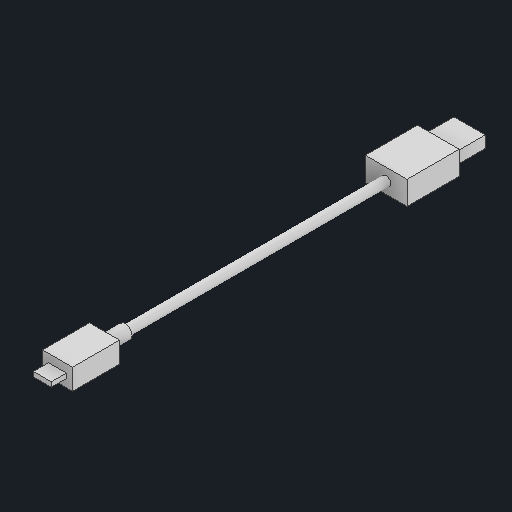
# Autodesk Inventor part: test_cable_microUSB_to_USBA
Saved by Autodesk Inventor 2027.1 (Build 311270010, 270A)
## iProperties
Created: 2026-10-29
Part Number: test_cable_microUSB_to_USBA
Material: Generic
Document SubType Name: Modeling
Designer: alexg
Density: 1 g/cm^3
Appearance: Default
Author: alexg
Autodesk Inventor part; units mm, degrees
ref_plane "Work Plane1" through (0, 0, -25.5) normal (0, 0, 1) x (1, 0, 0)
sketch "Micro-B shell sketch" plane through (0, 0, -25.5) normal (0, 0, 1) x (1, 0, 0)
  line L0 (-27.425, -26.74) -> (-20.575, -26.74)
  line L1 (-20.575, -26.74) -> (-20.575, -24.94)
  line L2 (-20.575, -24.94) -> (-27.425, -24.94)
  line L3 (-27.425, -24.94) -> (-27.425, -26.74)
  constraints: 8 end point, 2 parallel, 1 horizontal, 1 perpendicular
extrude "Micro-B shell" add sketch "Micro-B shell sketch" along normal blind 5.8
ref_plane "Work Plane2" through (0, 0, -25.5) normal (0, 0, 1) x (1, 0, 0)
sketch "Overmould 11.5x8x18 sketch" plane through (0, 0, -25.5) normal (0, 0, 1) x (1, 0, 0)
  line L0 (-29.75, -29.84) -> (-18.25, -29.84)
  line L1 (-18.25, -29.84) -> (-18.25, -21.84)
  line L2 (-18.25, -21.84) -> (-29.75, -21.84)
  line L3 (-29.75, -21.84) -> (-29.75, -29.84)
  constraints: 8 end point, 2 parallel, 1 horizontal, 1 perpendicular
extrude "Overmould 11.5x8x18" add sketch "Overmould 11.5x8x18 sketch" against normal blind 18
ref_plane "Work Plane3" through (0, 0, -43.5) normal (0, 0, 1) x (1, 0, 0)
sketch "Strain relief sketch" plane through (0, 0, -43.5) normal (0, 0, 1) x (1, 0, 0)
  circle A0 centre (-24, -25.84) radius 2.6
  constraints: 1 centre point
extrude "Strain relief" add sketch "Strain relief sketch" against normal blind 8
ref_plane "Work Plane4" through (0, 0, -51.5) normal (0, 0, 1) x (1, 0, 0)
sketch "Cable sketch" plane through (0, 0, -51.5) normal (0, 0, 1) x (1, 0, 0)
  circle A0 centre (-24, -25.84) radius 1.75
  constraints: 1 centre point
extrude "Cable" add sketch "Cable sketch" against normal blind 100
ref_plane "Work Plane5" through (0, 0, -151.5) normal (0, 0, 1) x (1, 0, 0)
sketch "USB-A overmould sketch" plane through (0, 0, -151.5) normal (0, 0, 1) x (1, 0, 0)
  line L0 (-32, -30.34) -> (-16, -30.34)
  line L1 (-16, -30.34) -> (-16, -21.34)
  line L2 (-16, -21.34) -> (-32, -21.34)
  line L3 (-32, -21.34) -> (-32, -30.34)
  constraints: 8 end point, 2 parallel, 1 horizontal, 1 perpendicular
extrude "USB-A overmould" add sketch "USB-A overmould sketch" against normal blind 20
ref_plane "Work Plane6" through (0, 0, -171.5) normal (0, 0, 1) x (1, 0, 0)
sketch "USB-A shell sketch" plane through (0, 0, -171.5) normal (0, 0, 1) x (1, 0, 0)
  line L0 (-30, -28.09) -> (-18, -28.09)
  line L1 (-18, -28.09) -> (-18, -23.59)
  line L2 (-18, -23.59) -> (-30, -23.59)
  line L3 (-30, -23.59) -> (-30, -28.09)
  constraints: 8 end point, 2 parallel, 1 horizontal, 1 perpendicular
extrude "USB-A shell" add sketch "USB-A shell sketch" against normal blind 12
body "Solid1"
